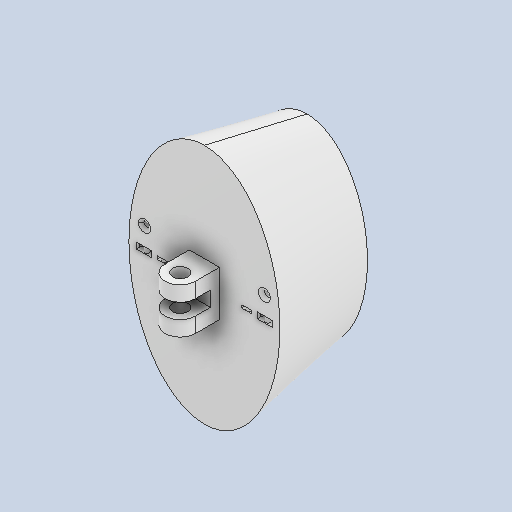
# Autodesk Inventor part: tail_segment_2
Saved by Autodesk Inventor 2026.1 (Build 301233020, 233B)
## iProperties
Created: 2025-11-11
Part Number: tail_segment_2
Material: Plastica ABS
Document SubType Name: Modeling
Designer: maxbu
Density: 1.06 g/cm^3
Appearance: Liscia - Bianco
Mass: 92.1585 g
Surface Area: 132.625 cm^2
Volume: 86.942 cm^3
Author: maxbu
Autodesk Inventor part; units mm, degrees
ref_plane "YZ Plane" through (0, 0, 0) normal (1, 0, 0) x (0, 1, 0)
sketch "Schizzo1" plane through (0, 0, 0) normal (1, 0, 0) x (0, 1, 0)
  line L0 (0, 0) -> (0, -5) construction
  line L1 (0, -5) -> (2.5, -5)
  line L2 (2.5, -5) -> (2.5, 5)
  line L3 (2.5, 5) -> (7.5, 5)
  line L4 (7.5, 5) -> (7.5, -8)
  line L5 (7.5, -8) -> (0, -8)
  line L6 (0, -5) -> (-2.5, -5)
  line L7 (-2.5, -5) -> (-2.5, 5)
  line L8 (-2.5, 5) -> (-7.5, 5)
  line L9 (-7.5, 5) -> (-7.5, -8)
  line L10 (-7.5, -8) -> (0, -8)
  line L11 (0, -8) -> (0, -42) construction
  line L12 (0, -42) -> (2.5, -42)
  line L13 (2.5, -42) -> (2.5, -55)
  line L14 (2.5, -55) -> (-2.5, -55)
  line L15 (-2.5, -55) -> (-2.5, -42)
  line L16 (-2.5, -42) -> (0, -42)
  line L17 (0, -42) -> (0, -50) construction
  dimension "d22" = 5
  dimension "d25" = 8
  dimension "d27" = 10
  dimension "d28" = 5
  dimension "d29" = 5
  dimension "d30" = 8
  dimension "d31" = 50
  dimension "d32" = 5
  dimension "d33" = 5
  constraints: 36 end point, 8 perpendicular, 4 symmetric about line, 2 collinear, 2 horizontal, 2 point on line, 2 vertical, 1 coincident
  measures "d22" distance of L0.start L0.end
  measures "d25" distance from line of L12 L17.end
  measures "d27" distance of L1.end L2.end
  measures "d28" distance between parallel lines of L7 L2
  measures "d29" distance of L2.end L3.end
  measures "d30" distance from line of L10 L0.start
  measures "d31" distance of L17.end L0.start
  measures "d32" distance of L13.end L14.end
  measures "d33" distance from line of L17.end L14
extrude "Estrusione1" add sketch "Schizzo1" along normal mid plane 10
sketch "Schizzo2" plane through (5, 7.5, -8) normal (0, 0, -1) x (-1, 0, 0)
  line L0 (5, -7.5) -> (5, -7.5) construction
  ellipse E0 centre (5, -7.5) end of major axis (5, 32.5) minor radius 25
  dimension "d2" = 40
  dimension "d3" = 25
  dimension "d4" = 0
  constraints: 2 end point, 1 coincident, 1 vertical, 2 other
  measures "d4" distance of L0.start L0.end
ref_plane "Piano di lavoro2" through (0, 0, -25) normal (0, 0, 1) x (1, 0, 0)
sketch "Schizzo4" plane through (0, 0, -25) normal (0, 0, 1) x (1, 0, 0)
  line L0 (0, 0) -> (0, 0) construction
  line L1 (-5, -2.5) -> (5, -2.5) projected
  ellipse E0 centre (0, 0) end of major axis (0, 36) minor radius 22
  dimension "d11" = 22
  dimension "d12" = 36
  dimension "d10" = 0
  constraints: 2 end point, 1 coincident, 1 perpendicular, 2 other
  measures "d10" distance of L0.start L0.end
sketch "Schizzo5" plane through (-5, -2.5, -42) normal (0, 0, 1) x (1, 0, 0)
  line L0 (5, 2.5) -> (5, 2.5) construction
  line L1 (0, 0) -> (10, 0) projected
  ellipse E0 centre (5, 2.5) end of major axis (5, 34.5) minor radius 20
  dimension "d14" = 20
  dimension "d15" = 32
  dimension "d13" = 0
  constraints: 2 end point, 1 coincident, 1 perpendicular, 2 other
  measures "d13" distance of L0.start L0.end
loft "Loft1" add profiles "Schizzo2", "Schizzo4", "Schizzo5"
fillet "Raccordo2" radius 5 6 edges at (5, 0, -55) (-5, 0, -55) (5, 5, 5) (-5, 5, 5) (5, -5, 5) (-5, -5, 5)
sketch "Schizzo8" plane through (-5, 7.5, -8) normal (0, 1, 0) x (1, 0, 0)
  arc A0 (10, 42) -> (0, 42) centre (5, 42) ccw projected
  point P0 (5, -8)
  constraints: 1 coincident
hole "Foro1" at (0, 7.5, -50) at (0, 7.5, 0) direction (0, -1, 0) diameter 5 end through all
ref_plane "Piano di lavoro3" through (0, 7, 0) normal (0, 1, 0) x (-1, 0, 0)
sketch "Schizzo10" plane through (0, 0, 0) normal (0, 1, 0) x (-1, 0, 0)
  circle A0 centre (-20, -9) radius 0.75
  arc A1 (-22.5, -9) -> (-17.5, -9) centre (-20, -9) ccw
  line L0 (25, -8) -> (-25, -8)
  line L1 (-22.5, -9) -> (-22.5, -8)
  line L2 (-17.5, -9) -> (-17.5, -8)
  line L3 (-17.5, -8) -> (-22.5, -8)
  line L4 (25, -8) -> (-25, -8) construction
  point P0 (0, -8)
  point P1 (0, -8)
  dimension "d55" = 1.5
  dimension "d56" = 5
  dimension "d57" = 1
  dimension "d58" = 20
  constraints: 8 end point, 2 centre point, 2 collinear, 2 perpendicular, 2 point on circle, 2 point on line, 2 tangent, 1 coincident, 1 horizontal, 1 midpoint
  measures "d55" diameter of A0
  measures "d56" diameter of A1
  measures "d57" distance of L1.start L1.end
  measures "d58" horizontal distance of point (0, -8) A0.centre
extrude "Estrusione3" cut sketch "Schizzo10" along normal mid plane 2
sketch "Schizzo9" plane through (0, 7, 0) normal (0, 1, 0) x (-1, 0, 0)
  line L0 (-20, -42) -> (20, -42) construction
  line L1 (-15, -42) -> (-20, -8)
  line L2 (-25, -8) -> (25, -8) construction
  line L3 (-16.0108, -42) -> (-21.0108, -8)
  line L4 (-21.0108, -8) -> (-20.0214, -7.8545)
  line L5 (-20.0214, -7.8545) -> (-20, -8)
  line L6 (-16.0108, -42) -> (-15.968, -42.291)
  line L7 (-15, -42) -> (-14.9786, -42.1455)
  line L8 (-15.968, -42.291) -> (-14.9786, -42.1455)
  line L9 (-14.9786, -42.1455) -> (-13.9892, -42) construction
  circle A0 centre (0, -50) radius 2.5 projected
  circle A1 centre (0, 0) radius 2.5 projected
  line L10 (0, -50) -> (0, 0) construction
  line L11 (25, -8) -> (-25, -8) construction
  line L12 (25, -8) -> (-25, -8) construction
  line L13 (20, -42) -> (-20, -42) construction
  line L14 (20, -42) -> (-20, -42) construction
  point P0 (0, 0)
  point P1 (0, -8)
  point P2 (0, -8)
  point P3 (0, -42)
  dimension "d49" = 15
  dimension "d50" = 20
  dimension "d51" = 1
  constraints: 27 end point, 6 point on line, 5 collinear, 5 equal length, 2 horizontal, 2 midpoint, 2 perpendicular, 1 vertical
  measures "d49" distance of point (0, -42) L1.start
  measures "d50" distance of L1.end point (0, -8)
  measures "d51" distance between parallel lines of L1 L3
revolve "Rivoluzione1" cut sketch "Schizzo9" angle 360 about axis through (15, 7, -42) along (0.145494, 0, 0.9893591) contours L7 L8 L6 L3 L4 L5 L1
mirror "Speculare1" about plane through (0, 0, 0) normal (1, 0, 0) of "Rivoluzione1", "Estrusione3"
fillet "Raccordo3" radius 1 6 edges at (18.9892, 7, -8) (-18.9892, 7, -8) (15, 6, -42) (15, 8, -42) (-15, 6, -42) (-15, 8, -42)
sketch "Schizzo11" plane through (0, 0, 0) normal (0, 1, 0) x (-1, 0, 0)
  circle A0 centre (14, -8.7) radius 0.7
  line L0 (25, -8) -> (-25, -8) projected
  circle A1 centre (14, -8.7) radius 1.7
  point P0 (0, 0)
  point P1 (0, -8)
  point P2 (0, -8)
  point P3 (12.4508, -8)
  point P4 (15.5492, -8)
  point P5 (14, -8)
  dimension "d61" = 1.4
  dimension "d62" = 14
  dimension "d63" = 1
  constraints: 2 centre point, 1 coincident, 1 midpoint, 1 tangent
  measures "d61" diameter of A0
  measures "d62" horizontal distance of point (0, -8) A0.centre
  measures "d63" radial gap between concentric circles of A0 A1
extrude "Estrusione4" cut sketch "Schizzo11" along normal mid plane 1 contours L0 A1 picked at (15.3507, -8.8334)
mirror "Speculare2" about plane through (0, 0, 0) normal (1, 0, 0) of "Estrusione4"
sketch "Schizzo12" plane through (0, 0, 0) normal (0, 1, 0) x (-1, 0, 0)
  circle A0 centre (13, -41.3) radius 0.7
  line L0 (20, -42) -> (-20, -42) projected
  circle A1 centre (13, -41.3) radius 1.7
  point P0 (0, 0)
  point P1 (0, -42)
  point P2 (0, -42)
  point P3 (14.5492, -42)
  point P4 (11.4508, -42)
  point P5 (13, -42)
  dimension "d66" = 1
  dimension "d67" = 1.4
  dimension "d68" = 13
  constraints: 2 centre point, 1 coincident, 1 midpoint, 1 tangent
  measures "d66" radial gap between concentric circles of A1 A0
  measures "d67" diameter of A0
  measures "d68" horizontal distance of point (0, -42) A0.centre
extrude "Estrusione5" cut sketch "Schizzo12" along normal mid plane 1 contours L0 A1 picked at (14.3507, -41.1666)
mirror "Speculare3" about plane through (0, 0, 0) normal (1, 0, 0) of "Estrusione5"
